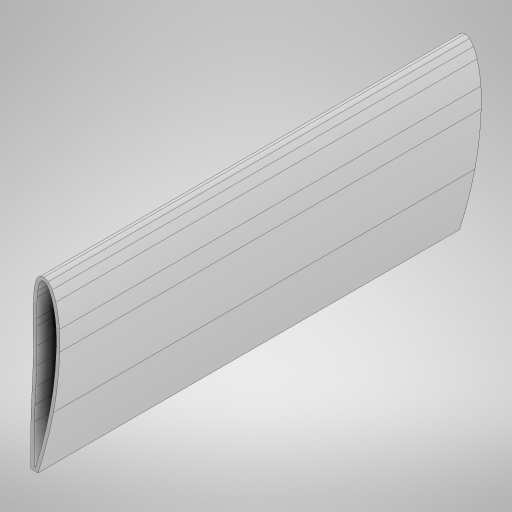
# Autodesk Inventor part: funda ala
Saved by Autodesk Inventor 2023 (Build 270158000, 158)
## iProperties
Created: 2023-05-20
Part Number: funda ala
Material: Genérico
Document SubType Name: Modeling
Designer: brand
Density: 1 g/cm^3
Appearance: Valor por defecto
Author: brand
Autodesk Inventor part; units mm, degrees
ref_plane "YZ Plane" through (0, 0, 0) normal (1, 0, 0) x (0, 1, 0)
ref_plane "XZ Plane" through (0, 0, 0) normal (0, 1, 0) x (-1, 0, 0)
ref_plane "Plano de trabajo1" through (-0.0141, 0, 0) normal (0, 0, 1) x (1, 0, 0)
sketch "Boceto1" plane through (-0.0141, 0, 0) normal (0, 0, 1) x (1, 0, 0)
  arc A0 (-7.4562, -56.0395) -> (-0.9933, -27.7778) centre (-428.1401, 55.0331) ccw projected
  line L0 (-7.4562, -56.0395) -> (-7.4562, -67.2646) projected
  arc A1 (-7.4562, -67.2646) -> (1.9523, -28.3464) centre (-428.1401, 55.0331) ccw projected
  arc A2 (1.9523, -28.3464) -> (7.344, 18.865) centre (-304.7846, 30.5972) ccw projected
  arc A3 (7.344, 18.865) -> (7.0999, 35.4811) centre (-151.6177, 24.84) ccw projected
  arc A4 (7.0999, 35.4811) -> (3.8884, 53.9102) centre (-82.0941, 29.4321) ccw projected
  arc A5 (3.8884, 53.9102) -> (0.8163, 61.541) centre (-35.1501, 42.6272) ccw projected
  arc A6 (0.8163, 61.541) -> (-2.5378, 65.7911) centre (-11.5056, 55.2655) ccw projected
  arc A7 (-2.5378, 65.7911) -> (-6.1787, 67.2615) centre (-6.6798, 60.7777) ccw projected
  arc A8 (-6.1787, 67.2615) -> (-7.4562, 67.1599) centre (-6.3675, 61.5521) ccw projected
  line L1 (-7.4562, 67.1599) -> (-7.4562, 64.0944) projected
  line L2 (-7.4562, 64.0944) -> (-6.9283, 64.206) projected
  arc A9 (-6.3419, 64.2645) -> (-6.9283, 64.206) centre (-6.3675, 61.5521) ccw projected
  arc A10 (-4.4645, 63.4914) -> (-6.3419, 64.2645) centre (-6.6798, 60.7777) ccw projected
  arc A11 (-1.8485, 60.1627) -> (-4.4645, 63.4914) centre (-11.5056, 55.2655) ccw projected
  arc A12 (1.0047, 53.0829) -> (-1.8485, 60.1627) centre (-35.1501, 42.6272) ccw projected
  arc A13 (4.1067, 35.2793) -> (1.0047, 53.0829) centre (-82.0941, 29.4321) ccw projected
  arc A14 (4.3461, 18.9766) -> (4.1067, 35.2793) centre (-151.6177, 24.84) ccw projected
  arc A15 (-0.9933, -27.7778) -> (4.3461, 18.9766) centre (-304.7846, 30.5972) ccw projected
  arc A16 (-7.7035, 63.9128) -> (-9.7278, 61.5272) centre (-5.4214, 59.9246) ccw projected
  arc A17 (-7.4562, 64.0365) -> (-7.7035, 63.9128) centre (-6.3675, 61.5521) ccw projected
  line L3 (-7.4562, 64.0365) -> (-7.4562, 67.1599) projected
  arc A18 (-7.4562, 67.1599) -> (-9.1877, 66.5199) centre (-6.3675, 61.5521) ccw projected
  arc A19 (-9.1877, 66.5199) -> (-12.5373, 62.5791) centre (-5.4214, 59.9246) ccw projected
  arc A20 (-12.5373, 62.5791) -> (-13.3197, 60.0958) centre (9.8334, 54.166) ccw projected
  arc A21 (-13.3197, 60.0958) -> (-14.3432, 55.1904) centre (19.9469, 50.5958) ccw projected
  arc A22 (-14.3432, 55.1904) -> (-14.8783, 49.883) centre (74.5564, 43.5456) ccw projected
  arc A23 (-14.8783, 49.883) -> (-15.4143, 33.6997) centre (203.1104, 34.5632) ccw projected
  line L4 (-15.4143, 33.6997) -> (-15.3763, 27.9897) projected
  line L5 (-15.3763, 27.9897) -> (-15.1533, 13.7591) projected
  arc A24 (-15.3266, -0.8615) -> (-15.1533, 13.7591) centre (-328.0599, 10.1572) ccw projected
  arc A25 (-16.0201, -16.7159) -> (-15.3266, -0.8615) centre (-897.7232, 29.7896) ccw projected
  line L6 (-16.0201, -16.7159) -> (-16.732, -30.3625) projected
  arc A26 (-16.732, -30.3625) -> (-17.1616, -42.9645) centre (475.4107, -53.4474) ccw projected
  arc A27 (-17.1616, -42.9645) -> (-17.3834, -79.3654) centre (955.158, -67.0907) ccw projected
  line L7 (-17.3834, -79.3654) -> (-13.4984, -79.569) projected
  line L8 (-13.4984, -79.569) -> (-11.2302, -79.569) projected
  arc A28 (-11.2302, -79.569) -> (-7.4562, -67.2646) centre (-428.1401, 55.0331) ccw projected
  line L9 (-7.4562, -67.2646) -> (-7.4562, -56.0395) projected
  arc A29 (-13.4198, -76.569) -> (-7.4562, -56.0395) centre (-428.1401, 55.0331) ccw projected
  line L10 (-13.4198, -76.569) -> (-14.415, -76.5169) projected
  arc A30 (-14.1624, -43.0336) -> (-14.415, -76.5169) centre (955.158, -67.0907) ccw projected
  arc A31 (-13.7357, -30.5109) -> (-14.1624, -43.0336) centre (475.4107, -53.4474) ccw projected
  line L11 (-13.7357, -30.5109) -> (-13.0242, -16.8731) projected
  arc A32 (-13.0242, -16.8731) -> (-12.3285, -0.9664) centre (-897.7232, 29.7896) ccw projected
  arc A33 (-12.3285, -0.9664) -> (-12.1536, 13.7998) centre (-328.0599, 10.1572) ccw projected
  line L12 (-12.1536, 13.7998) -> (-12.3765, 28.0232) projected
  line L13 (-12.3765, 28.0232) -> (-12.4143, 33.7155) projected
  arc A34 (-11.8858, 49.6718) -> (-12.4143, 33.7155) centre (203.1104, 34.5632) ccw projected
  arc A35 (-11.3692, 54.7963) -> (-11.8858, 49.6718) centre (74.5564, 43.5456) ccw projected
  arc A36 (-10.4236, 59.312) -> (-11.3692, 54.7963) centre (19.9469, 50.5958) ccw projected
  arc A37 (-9.7278, 61.5272) -> (-10.4236, 59.312) centre (9.8334, 54.166) ccw projected
  line L14 (-17.3834, -79.3654) -> (-17.3834, -88.4624)
  line L15 (-17.3834, -88.4624) -> (-17.3834, -97.317)
  line L16 (-17.3834, -97.317) -> (-11.2302, -79.569)
  point P0 (0.0141, 0)
  point P1 (7.344, 18.865)
  point P2 (-17.3834, -79.3654)
  constraints: 6 end point, 2 vertical
extrude "Extrusión1" add sketch "Boceto1" along normal blind 358.75 contours A0 A15 A14 A13 A12 A11 A10 A9 L2 L1 A8 A7 A6 A5 A4 A3 A2 A1 L0 | L0 A28 L8 L7 A27 A26 L6 A25 A24 L5 L4 A23 A22 A21 A20 A19 A18 L1 L3 A17 A16 A37 A36 A35 A34 L13 L12 A33 A32 L11 A31 A30 L10 A29
